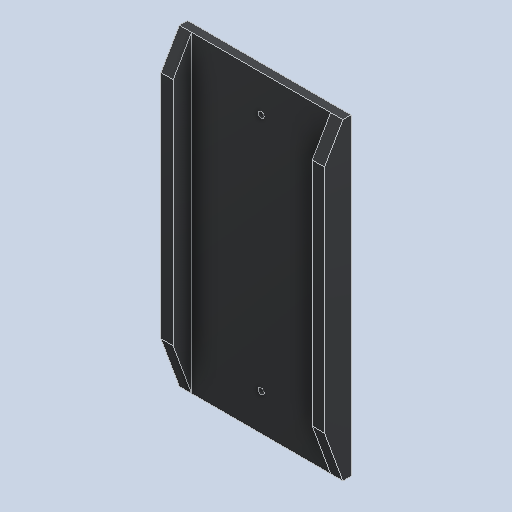
# Autodesk Inventor part: Desviador
Saved by Autodesk Inventor 2025.3 (Build 293356000, 356)
## iProperties
Created: 2026-11-22
Part Number: Desviador
Material: PLA (ácido poliláctico) - FDM nominal
Document SubType Name: Modeling
Designer: STEVEN LONDOÑO
Density: 1.24 g/cm^3
Appearance: PLA negro mate - capas FDM
Author: STEVEN LONDOÑO
Autodesk Inventor part; units mm, degrees
ref_plane "YZ Plane" through (0, 0, 0) normal (1, 0, 0) x (0, 1, 0)
ref_plane "XZ Plane" through (0, 0, 0) normal (0, 1, 0) x (-1, 0, 0)
ref_plane "XY Plane" through (0, 0, 0) normal (0, 0, 1) x (1, 0, 0)
sketch "Boceto1" plane through (0, 0, 0) normal (0, 0, 1) x (1, 0, 0)
  line L0 (-40, 76.5) -> (40, 76.5)
  line L1 (40, 76.5) -> (40, -76.5)
  line L2 (40, -76.5) -> (-40, -76.5)
  line L3 (-40, -76.5) -> (-40, 76.5)
  line L4 (40, 76.5) -> (34, 76.5)
  line L5 (34, 76.5) -> (34, -76.5)
  line L6 (-40, 76.5) -> (-34, 76.5)
  line L7 (-34, 76.5) -> (-34, -76.5)
  point P0 (0, 0)
  point P1 (0, 76.5)
  point P2 (-40, 0)
  dimension "d0" = 153
  dimension "d1" = 80
  dimension "d2" = 6
  dimension "d3" = 6
  constraints: 16 end point, 4 point on line, 3 perpendicular, 2 midpoint, 2 parallel, 1 horizontal, 1 horizontal alignment, 1 vertical alignment
  measures "d0" distance of L0.end L1.end
  measures "d1" distance of L1.end L2.end
  measures "d2" distance of L0.end L4.end
  measures "d3" distance of L0.start L6.end
extrude "Extrusión1" add sketch "Boceto1" along normal blind 4 contours L0 L5 L2 L7
extrude "Extrusión2" add sketch "Boceto1" along normal blind 13 contours L0 L7 L2 L3 | L0 L1 L2 L5
sketch "Boceto3" plane through (-40, -76.5, 0) normal (-1, 0, 0) x (0, 0, 1)
  line L0 (0, 0) -> (0, 153) projected
  line L1 (0, 153) -> (4, 153)
  line L2 (0, 153) -> (13, 153) projected
  line L3 (4, 153) -> (11.6809, 139.6964)
  line L4 (4, 153) -> (19.3617, 153) construction
  line L5 (11.6809, 139.6964) -> (13, 137.4115)
  line L6 (13, 0) -> (13, 153) projected
  line L7 (4, 153) -> (13, 153)
  line L8 (13, 153) -> (13, 137.4115)
  point P0 (0, 76.5)
  dimension "d10" = 4
  dimension "d11" = 60
  constraints: 12 end point, 3 point on line, 2 collinear, 1 equal length, 1 horizontal
  measures "d10" distance of L0.end L1.end
  measures "d11" angle of L3 L4
extrude "Extrusión3" cut sketch "Boceto3" against normal blind 100
sketch "Boceto4" plane through (-40, -76.5, 0) normal (-1, 0, 0) x (0, 0, 1)
  line L0 (0, 0) -> (13, 0) projected
  line L1 (0, 0) -> (4, 0)
  line L2 (4, 0) -> (10.7505, 18.547)
  line L3 (4, 0) -> (23.7373, 0) construction
  line L4 (10.7505, 18.547) -> (13, 24.7273)
  line L5 (13, 0) -> (13, 137.4115) projected
  line L6 (13, 0) -> (4, 0)
  point P0 (0, 76.5)
  dimension "d14" = 4
  dimension "d15" = 70
  constraints: 10 end point, 2 point on line, 1 collinear, 1 equal length, 1 horizontal
  measures "d14" distance of L0.start L1.end
  measures "d15" angle of L3 L2
extrude "Extrusión4" cut sketch "Boceto4" against normal blind 100
sketch "Boceto9" plane through (0, 0, 0) normal (0, 0, -1) x (-1, 0, 0)
  circle A0 centre (0, 58.5) radius 1.5 projected
  circle A1 centre (0, 58.5) radius 2.9
  point P0 (0, 0)
  constraints: 1 centre point, 1 coincident
extrude "Extrusión9" cut sketch "Boceto9" against normal blind 2
extrude "Extrusión10" cut sketch "Boceto9" against normal blind 4 contours A0
sketch "Boceto10" plane through (0, 0, 0) normal (0, 0, -1) x (-1, 0, 0)
  line L0 (34, -76.5) -> (-34, -76.5) projected
  line L1 (0, -76.5) -> (0, -58.5)
  circle A0 centre (0, -58.5) radius 2.9
  circle A1 centre (0, -58.5) radius 1.5
  point P0 (0, 0)
  dimension "d39" = 18
  dimension "d40" = 5.8
  dimension "d41" = 3
  constraints: 2 centre point, 2 coincident, 2 end point, 1 midpoint, 1 vertical
  measures "d39" distance of L1.start L1.end
  measures "d40" diameter of A0
  measures "d41" diameter of A1
extrude "Extrusión11" cut sketch "Boceto10" against normal blind 2
extrude "Extrusión12" cut sketch "Boceto10" against normal blind 4 contours A1
